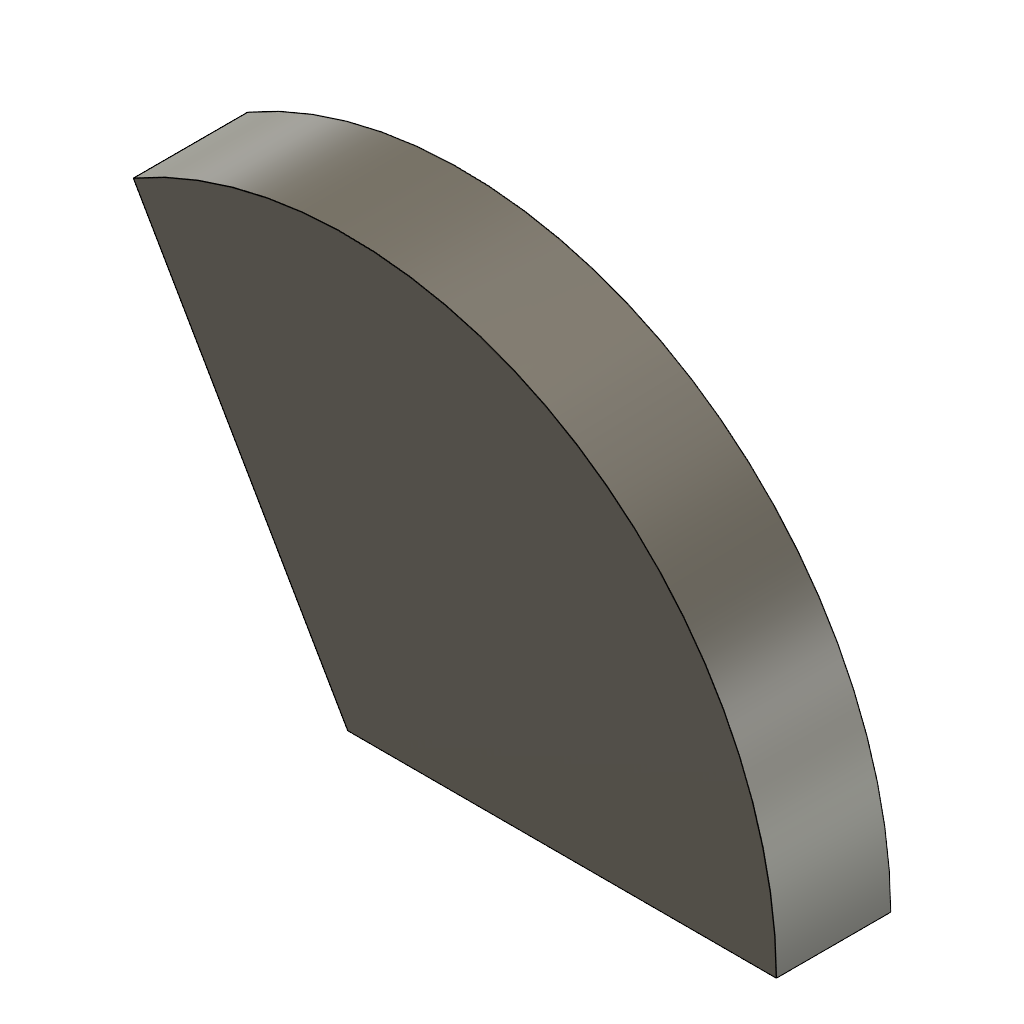
sk_arc_center_start_end (Autodesk Fusion 360 design; units mm, degrees)
part number: 2026-11-13-14-35-17-890
Autodesk Fusion 360 part; units mm, degrees
sketch "Sketch1" plane through (0, 0, 0) normal (0, 0, 1) x (1, 0, 0)
  arc A0 (15, 0) -> (-7.5, 12.9904) centre (0, 0) ccw
  line L0 (-7.5, 12.9904) -> (0, 0)
  line L1 (0, 0) -> (15, 0)
extrude "Extrude1" add sketch "Sketch1" along normal blind 4
